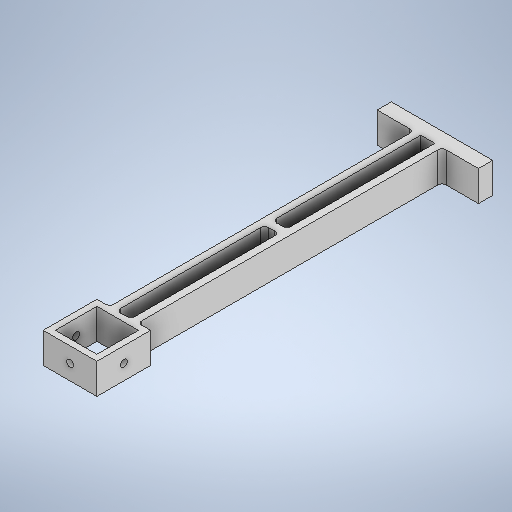
# Autodesk Inventor part: Sujetador_Camara_15_cm
Saved by Autodesk Inventor 2025.3 (Build 293356030, 356C)
## iProperties
Created: 2026-06-04
Part Number: Sujetador_Camara_15_cm
Material: Generic
Document SubType Name: Modeling
Designer: pablo
Density: 1 g/cm^3
Appearance: Default
Author: pablo
Autodesk Inventor part; units mm, degrees
ref_plane "YZ Plane" through (0, 0, 0) normal (1, 0, 0) x (0, 1, 0)
ref_plane "XZ Plane" through (0, 0, 0) normal (0, 1, 0) x (-1, 0, 0)
ref_plane "XY Plane" through (0, 0, 0) normal (0, 0, 1) x (1, 0, 0)
sketch "Sketch1" plane through (0, 0, 0) normal (0, 1, 0) x (-1, 0, 0)
  line L0 (3, -3) -> (23.5, -3)
  line L1 (23.5, -3) -> (23.5, -23.5)
  line L2 (23.5, -23.5) -> (3, -23.5)
  line L3 (3, -23.5) -> (3, -3)
  line L4 (26.5, 0) -> (0, 0)
  line L5 (0, 0) -> (0, -26.5)
  line L6 (0, -26.5) -> (26.5, -26.5)
  line L7 (26.5, -26.5) -> (26.5, 0)
  dimension "d0" = 20.5
  dimension "d1" = 3
  dimension "d2" = 3
  dimension "d3" = 3
  dimension "d4" = 3
  constraints: 16 end point, 4 parallel, 3 perpendicular, 2 horizontal, 1 coincident
  measures "d0" distance of L1.end L2.end
  measures "d1" distance between parallel lines of L5 L3
  measures "d2" distance between parallel lines of L6 L2
  measures "d3" distance between parallel lines of L1 L7
  measures "d4" distance between parallel lines of L0 L4
extrude "Extrusion1" add sketch "Sketch1" along normal blind 15
sketch "Sketch2" plane through (0, 0, 0) normal (1, 0, 0) x (0, 0, -1)
  line L0 (0, 0) -> (26.5, 0) projected
  line L1 (26.5, 0) -> (26.5, 15) projected
  line L2 (0, 15) -> (26.5, 15) projected
  line L3 (0, 0) -> (0, 15) projected
  point P0 (13.25, 7.5)
  point P1 (0, 7.5)
  point P2 (13.25, 15)
  constraints: 2 midpoint, 1 horizontal alignment, 1 vertical alignment
hole "Hole1" at (0, 7.5, -13.25) direction (-1, 0, 0) diameter 3.4 depth 26.5
sketch "Sketch3" plane through (-26.5, 0, 0) normal (0, 0, 1) x (1, 0, 0)
  line L0 (0, 0) -> (26.5, 0) projected
  line L1 (26.5, 0) -> (26.5, 15) projected
  line L2 (0, 15) -> (26.5, 15) projected
  line L3 (0, 0) -> (0, 15) projected
  point P0 (13.25, 7.5)
  point P1 (0, 7.5)
  point P2 (13.25, 15)
  constraints: 2 midpoint, 1 horizontal alignment, 1 vertical alignment
hole "Hole2" at (-13.25, 7.5, 0) direction (0, 0, -1) diameter 3.4 depth 3
sketch "Sketch4" plane through (0, 0, -26.5) normal (0, 0, -1) x (-1, 0, 0)
  line L0 (0, 0) -> (26.5, 0) projected
  line L1 (26.5, 0) -> (26.5, 15) projected
  line L2 (0, 15) -> (26.5, 15) projected
  line L3 (0, 0) -> (0, 15) projected
  line L4 (3, 0) -> (23.5, 0) projected
  line L5 (20.25, 0) -> (20.25, 15)
  line L6 (6.25, 0) -> (6.25, 15)
  line L7 (16.75, 0) -> (16.75, 15)
  line L8 (9.75, 0) -> (9.75, 15)
  point P0 (0, 0)
  point P1 (13.25, 0)
  dimension "d21" = 7
  dimension "d22" = 14
  dimension "d25" = 3.5
  dimension "d26" = 7
  constraints: 8 end point, 8 point on line, 4 perpendicular, 1 midpoint
  measures "d21" distance from line of point (13.25, 0) L6
  measures "d22" distance between parallel lines of L5 L6
  measures "d25" distance between parallel lines of L6 L8
  measures "d26" distance between parallel lines of L7 L8
extrude "Extrusion2" add sketch "Sketch4" along normal blind 150 contours L6 L2 L8 L0 | L7 L2 L5 L0
sketch "Sketch5" plane through (0, 15, 0) normal (0, 1, 0) x (1, 0, 0)
  line L0 (0, 0) -> (0, 26.5) projected
  line L1 (0, 26.5) -> (-6.25, 26.5) projected
  line L2 (-6.25, 26.5) -> (-6.25, 176.5) projected
  line L3 (-9.75, 176.5) -> (-6.25, 176.5) projected
  line L4 (-9.75, 26.5) -> (-9.75, 176.5) projected
  line L5 (-9.75, 26.5) -> (-16.75, 26.5) projected
  line L6 (-16.75, 26.5) -> (-16.75, 176.5) projected
  line L7 (-20.25, 176.5) -> (-16.75, 176.5) projected
  line L8 (-20.25, 26.5) -> (-20.25, 176.5) projected
  line L9 (-20.25, 26.5) -> (-26.5, 26.5) projected
  line L10 (-26.5, 26.5) -> (-26.5, 0) projected
  line L11 (-26.5, 0) -> (0, 0) projected
  line L12 (-3, 3) -> (-23.5, 3) projected
  line L13 (-23.5, 3) -> (-23.5, 23.5) projected
  line L14 (-23.5, 23.5) -> (-3, 23.5) projected
  line L15 (-3, 23.5) -> (-3, 3) projected
  line L16 (-9.75, 99.5) -> (-16.75, 99.5)
  line L17 (-9.75, 26.5) -> (-9.75, 176.5) projected
  line L18 (-9.75, 103.5) -> (-16.75, 103.5)
  point P0 (-16.75, 101.5)
  point P1 (-9.75, 103.5)
  dimension "d27" = 2
  dimension "d28" = 4
  constraints: 4 end point, 4 point on line, 2 perpendicular, 1 midpoint
  measures "d27" distance from line of point (-16.75, 101.5) L16
  measures "d28" distance between parallel lines of L18 L16
extrude "Extrusion3" add sketch "Sketch5" against normal up to surface (15 mm away) contours L4 L16 L6 L18
sketch "Sketch6" plane through (0, 0, -176.5) normal (0, 0, -1) x (-1, 0, 0)
  line L0 (9.75, 15) -> (6.25, 15) projected
  line L1 (6.25, 15) -> (6.25, 0) projected
  line L2 (6.25, 0) -> (9.75, 0) projected
  line L3 (9.75, 0) -> (9.75, 15) projected
  line L4 (16.75, 0) -> (20.25, 0) projected
  line L5 (20.25, 0) -> (20.25, 15) projected
  line L6 (20.25, 15) -> (16.75, 15) projected
  line L7 (16.75, 15) -> (16.75, 0) projected
  line L8 (-11.75, 15) -> (38.25, 15)
  line L9 (38.25, 15) -> (38.25, 0)
  line L10 (38.25, 0) -> (-11.75, 0)
  line L11 (-11.75, 0) -> (-11.75, 15)
  line L12 (9.75, 15) -> (16.75, 15) projected
  point P0 (0, 0)
  point P1 (13.25, 15)
  point P2 (6.25, 0)
  point P3 (9.75, 0)
  point P4 (16.75, 0)
  point P5 (20.25, 0)
  dimension "d31" = 50
  constraints: 8 end point, 3 parallel, 2 midpoint, 1 horizontal, 1 perpendicular
  measures "d31" distance of L8.start L8.end
extrude "Extrusion4" add sketch "Sketch6" along normal blind 7
fillet "Fillet1" radius 2 10 edges at (-20.25, 7.5, -176.5) (-6.25, 7.5, -176.5) (-16.75, 7.5, -99.5) (-9.75, 7.5, -99.5) (-16.75, 7.5, -103.5) (-9.75, 7.5, -103.5) (-20.25, 7.5, -26.5) (-16.75, 7.5, -26.5) (-9.75, 7.5, -26.5) (-6.25, 7.5, -26.5)
sketch "Sketch7" plane through (0, 0, -183.5) normal (0, 0, -1) x (-1, 0, 0)
  line L0 (38.25, 15) -> (-11.75, 15) projected
  line L1 (-11.75, 15) -> (-11.75, 0) projected
  line L2 (-11.75, 0) -> (38.25, 0) projected
  line L3 (38.25, 0) -> (38.25, 15) projected
  point P0 (0, 0)
  point P1 (13.25, 7.5)
  point P2 (38.25, 7.5)
  dimension "d35" = 25
  constraints: 1 horizontal alignment, 1 midpoint
  measures "d35" distance from line of L3 point (13.25, 7.5)
hole "Hole3" at (-13.25, 7.5, -183.5) direction (0, 0, 1) diameter 3.4 depth 7
sketch "Sketch8" plane through (0, 0, -176.5) normal (0, 0, 1) x (1, 0, 0)
  circle A0 centre (-13.25, 7.5) radius 1.7 projected
  line L0 (-9.75, 0) -> (-9.75, 15) projected
  line L1 (-16.75, 15) -> (-9.75, 15) projected
  line L2 (-16.75, 15) -> (-16.75, 0) projected
  line L3 (-9.75, 0) -> (-16.75, 0) projected
  line L4 (-13.25, 10.7332) -> (-10.45, 9.1166)
  line L5 (-10.45, 9.1166) -> (-10.45, 5.8834)
  line L6 (-10.45, 5.8834) -> (-13.25, 4.2668)
  line L7 (-13.25, 4.2668) -> (-16.05, 5.8834)
  line L8 (-16.05, 5.8834) -> (-16.05, 9.1166)
  line L9 (-16.05, 9.1166) -> (-13.25, 10.7332)
  line L10 (-16.75, 15) -> (-16.75, 0) projected
  point P0 (0, 0)
  dimension "d43" = 5.6
  constraints: 12 end point, 1 coincident, 1 parallel, 13 other
  measures "d43" distance between parallel lines of L6 L9
sketch "Sketch9" plane through (0, 0, -183.5) normal (0, 0, -1) x (-1, 0, 0)
  circle A0 centre (13.25, 7.5) radius 1.7 projected
  line L0 (38.25, 15) -> (-11.75, 15) projected
  line L1 (-11.75, 15) -> (-11.75, 0) projected
  line L2 (-11.75, 0) -> (38.25, 0) projected
  line L3 (38.25, 0) -> (38.25, 15) projected
  line L4 (-7.75, 13) -> (34.25, 13)
  line L5 (34.25, 13) -> (34.25, 2)
  line L6 (34.25, 2) -> (-7.75, 2)
  line L7 (-7.75, 2) -> (-7.75, 13)
  line L8 (-7.75, 13) -> (34.25, 2) construction
  line L9 (34.25, 13) -> (-7.75, 2) construction
  point P0 (0, 0)
  dimension "d44" = 42
  dimension "d45" = 11
  constraints: 12 end point, 2 midpoint, 2 parallel, 1 horizontal, 1 perpendicular
  measures "d44" distance of L5.end L6.end
  measures "d45" distance of L4.end L5.end
extrude "Extrusion5" cut sketch "Sketch9" against normal blind 3 contours L4 L5 L6 L7
extrude "Extrusion6" cut sketch "Sketch8" against normal blind 2.6 contours L4 L5 L6 L7 L8 L9
equation "\"d22\" = 2 * d21"
equation "\"d25\" = 0.5 * d21"
equation "\"d26\" = 2 * d25"
equation "\"d28\" = 2 * d27"
body "Solid1"
